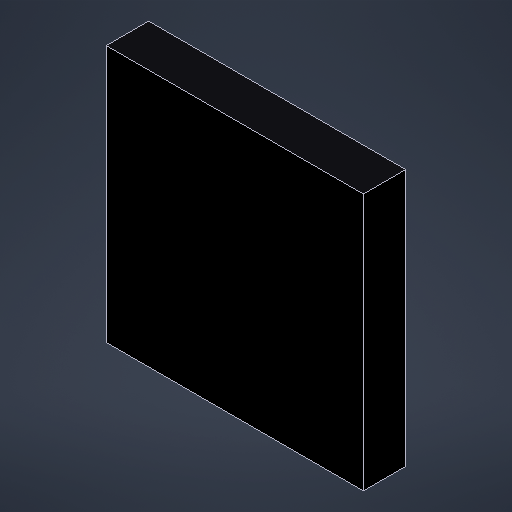
# Autodesk Inventor part: ref_oled
Saved by Autodesk Inventor 2027.1 (Build 311270010, 270A)
## iProperties
Created: 2026-10-22
Part Number: ref_oled
Material: 일반
Document SubType Name: Modeling
Designer: sungjun
Density: 1 g/cm^3
Appearance: ref_oled_c
Author: sungjun
Autodesk Inventor part; units mm, degrees
ref_plane "YZ Plane" through (0, 0, 0) normal (1, 0, 0) x (0, 1, 0)
ref_plane "XZ Plane" through (0, 0, 0) normal (0, 1, 0) x (-1, 0, 0)
ref_plane "작업 평면1" through (0, 0, 54.25) normal (0, 0, 1) x (1, 0, 0)
sketch "스케치1" plane through (0, 0, 54.25) normal (0, 0, 1) x (1, 0, 0)
  line L0 (10, 4) -> (37.3, 4)
  line L1 (37.3, 4) -> (37.3, 31.3)
  line L2 (37.3, 31.3) -> (10, 31.3)
  line L3 (10, 31.3) -> (10, 4)
  constraints: 8 end point, 2 parallel, 1 horizontal, 1 perpendicular
extrude "돌출1" add sketch "스케치1" along normal mid plane 4.5
